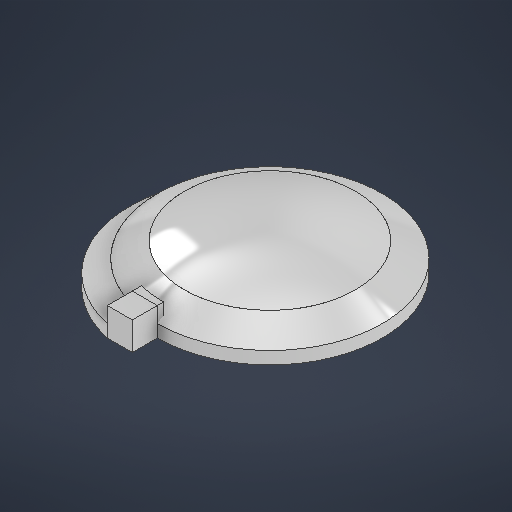
# Autodesk Inventor part: aluminumRing
Saved by Autodesk Inventor 2027.1 (Build 311270010, 270A)
## iProperties
Created: 2026-11-09
Part Number: aluminumRing
Material: ABS Plastic
Document SubType Name: Modeling
Designer: Operator
Density: 1.06 g/cm^3
Appearance: Aluminum - Polished
Mass: 3396.5 g
Surface Area: 5629.59 cm^2
Volume: 3204.24 cm^3
Author: Operator
Autodesk Inventor part; units mm, degrees
ref_plane "YZ Plane" through (0, 0, 0) normal (1, 0, 0) x (0, 1, 0)
sketch "Sketch1" plane through (0, 0, 0) normal (0, 1, 0) x (-1, 0, 0)
  circle A0 centre (0, 0) radius 228.6
  dimension "d0" = 457.2
  constraints: 1 centre point, 1 coincident
  measures "d0" diameter of A0
extrude "Extrusion1" add sketch "Sketch1" along normal blind 25.4
sketch "Sketch2" plane through (0, 25.4, 0) normal (0, 1, 0) x (1, 0, 0)
  circle A0 centre (0, 0) radius 228.6
  circle A1 centre (0, 0) radius 215.9
  dimension "d9" = 431.8
  constraints: 2 centre point, 2 coincident
  measures "d9" diameter of A1
ref_plane "Work Plane1" through (0, 57.15, 0) normal (0, 1, 0) x (1, 0, 0)
extrude "Extrusion2" cut sketch "Sketch2" against normal blind 25.4 contours A1
sketch "Sketch4" plane through (0, 0, 0) normal (0, 0, 1) x (1, 0, 0)
  line L0 (228.6, 25.4) -> (-228.6, 25.4) projected
  line L1 (-228.6, 25.4) -> (-173.6074, 57.15)
  line L2 (-228.6, 25.4) -> (81.3709, 25.4) construction
  line L3 (-173.6074, 25.4) -> (-173.6074, 57.15)
  line L4 (-173.6074, 57.15) -> (-173.6074, 57.15)
  line L5 (-173.6074, 57.15) -> (-148.2074, 57.15)
  line L6 (-148.2074, 57.15) -> (-148.2074, 44.45)
  line L7 (-148.2074, 44.45) -> (-173.6074, 44.45)
  line L8 (0, -11.43) -> (0, 68.58) projected
  point P0 (0, 0)
  dimension "d12" = 30
  dimension "d13" = 31.75
  dimension "d14" = 25.4
  dimension "d15" = 12.7
  constraints: 14 end point, 3 perpendicular, 2 horizontal, 2 point on line, 1 vertical
  measures "d12" angle of L2 L1
  measures "d13" distance of L3.start L3.end
  measures "d14" distance of L3.end L5.end
  measures "d15" distance of L5.end L6.end
revolve "Revolution1" add sketch "Sketch4" angle 360 about axis through (0, -10, 0) along (0, 1, 0)
sketch "Sketch5" plane through (0, 0, 0) normal (0, 0, 1) x (1, 0, 0)
  line L0 (0, -661.1506) -> (0, 213.8692) projected
  line L1 (0, 69.85) -> (0, 82.55)
  line L2 (173.6074, 44.45) -> (-173.6074, 44.45) projected
  arc A0 (0, 82.55) -> (-173.6074, 57.15) centre (0, -523.4477) ccw
  arc A1 (0, 69.85) -> (-123.4141, 57.15) centre (0, -536.1477) ccw
  line L3 (-173.6074, 57.15) -> (-123.4141, 57.15)
  point P0 (0, 0)
  constraints: 4 end point, 4 point on circle, 2 centre point, 2 point on line
revolve "Revolution2" add sketch "Sketch5" angle 360 about axis through (0, -10, 0) along (0, 1, 0) separate body
ref_plane "Work Plane2" through (0, 0, 228.6) normal (0, 0, 1) x (1, 0, 0)
sketch "Sketch6" plane through (0, 0, 228.6) normal (0, 0, 1) x (1, 0, 0)
  line L0 (173.6074, 57.15) -> (-173.6074, 57.15) projected
  line L1 (0, 0) -> (-50.8, 0)
  line L2 (-50.8, 0) -> (-50.8, 57.15)
  line L3 (-50.8, 57.15) -> (0, 57.15)
  line L4 (0, 57.15) -> (0, 0)
  dimension "d23" = 50.8
  constraints: 8 end point, 2 parallel, 1 horizontal, 1 perpendicular, 1 point on line
  measures "d23" distance of L2.end L3.end
extrude "Extrusion3" add sketch "Sketch6" against normal up to surface separate body round surface about axis through (0, 25.4, 0) along (0, -1, 0) radius 215.9 far side no
sketch "Sketch7" plane through (0, 0, 228.6) normal (0, 0, 1) x (1, 0, 0)
  line L0 (0, 0) -> (0, 57.15) projected
  line L1 (-50.8, 57.15) -> (-50.8, 0) projected
  line L2 (0, 0) -> (-50.8, 0)
  line L3 (-50.8, 0) -> (-50.8, 57.15)
  line L4 (-50.8, 57.15) -> (0, 57.15)
  line L5 (0, 57.15) -> (0, 0)
  constraints: 8 end point, 2 parallel, 1 horizontal, 1 perpendicular
extrude "Extrusion4" add sketch "Sketch7" along normal blind 50.8 separate body
sketch "Sketch8" plane through (0, 0, 0) normal (0, -1, 0) x (1, 0, 0)
  circle A0 centre (0, 0) radius 228.6 projected
  line L0 (0, 279.4) -> (-50.8, 279.4) projected
  arc A1 (-50.8, 279.4) -> (-228.6, 0) centre (0, 50.8) ccw
  arc A2 (-50.8, 222.8841) -> (-228.6, 0) centre (0, 0) ccw
  line L1 (-50.8, 279.4) -> (-50.8, 222.8841)
  line L2 (-50.8, 228.6) -> (0, 228.6) projected
  point P0 (0, 228.6)
  constraints: 7 point on circle, 2 centre point, 2 concentric, 2 end point, 1 point on line, 1 vertical, 1 other
extrude "Extrusion5" add sketch "Sketch8" against normal blind 25.4 separate body contours A1 L1 A0
body "Solid3"
body "Solid4"
body "Solid5"
